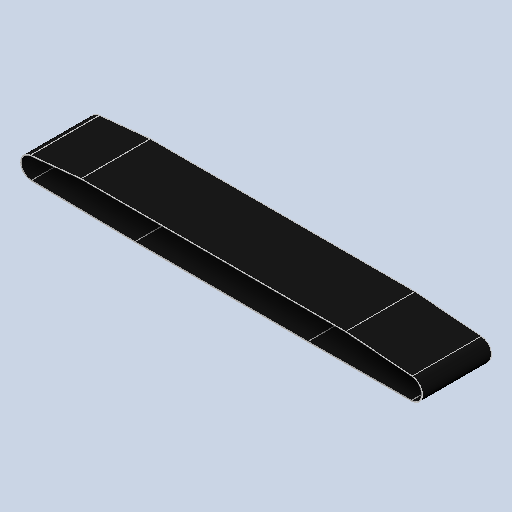
# Autodesk Inventor part: Banda
Saved by Autodesk Inventor 2025.3 (Build 293356000, 356)
## iProperties
Created: 2026-09-16
Part Number: Banda
Material: Hule SBR reforzado con tela
Document SubType Name: Modeling
Designer: ASUS
Density: 1.33 g/cm^3
Appearance: Hule negro mate - grano fino
Mass: 159.181 g
Surface Area: 2417.64 cm^2
Volume: 119.685 cm^3
Author: ASUS
Autodesk Inventor part; units mm, degrees
ref_plane "YZ Plane" through (0, 0, 0) normal (1, 0, 0) x (0, 1, 0)
ref_plane "XZ Plane" through (0, 0, 0) normal (0, 1, 0) x (-1, 0, 0)
ref_plane "XY Plane" through (0, 0, 0) normal (0, 0, 1) x (1, 0, 0)
sketch "Boceto1" plane through (0, 0, 0) normal (0, 0, 1) x (1, 0, 0)
  arc A0 (275.2379, 12.4594) -> (275.308, 45.9161) centre (275.308, 29.1877) ccw
  line L0 (275.2379, 12.4594) -> (-274.7368, 12.4594)
  arc A1 (-274.7368, 45.4594) -> (-274.7368, 12.4594) centre (-274.7368, 28.9594) ccw
  line L1 (275.308, 45.9161) -> (275.308, 45.9161)
  line L2 (-214.7369, 51.8594) -> (194.2632, 51.8594)
  line L3 (-274.7368, 45.4594) -> (-214.7369, 51.8594)
  line L4 (194.2632, 51.8594) -> (275.308, 45.9161)
  point P0 (0, 0)
  point P1 (0, 13.9594)
  constraints: 10 end point, 5 point on circle, 2 centre point, 1 horizontal, 1 vertical alignment
extrude "Extrusión1" [suppressed]
sketch "Boceto4" plane through (0, 0, 100) normal (0, 0, 1) x (1, 0, 0)
  arc A0 (-274.7368, 45.4594) -> (-274.7368, 12.4594) centre (-274.7368, 28.9594) ccw projected
  line L0 (-274.7368, 45.4594) -> (-274.7368, 44.4594)
  line L1 (-274.7368, 12.4594) -> (-274.7368, 13.4594)
  arc A1 (-274.7368, 44.4594) -> (-274.7368, 13.4594) centre (-274.7368, 28.9594) ccw
  arc A2 (275.2379, 12.4594) -> (275.308, 45.9161) centre (275.308, 29.1877) ccw projected
  line L2 (275.308, 45.9161) -> (275.308, 44.9161)
  line L3 (275.2379, 12.4594) -> (275.2379, 13.4594)
  arc A3 (275.2379, 13.4594) -> (275.308, 44.9161) centre (275.0173, 29.1883) ccw
  line L4 (-274.7368, 12.4594) -> (275.2379, 12.4594) projected
  line L5 (275.2379, 13.4594) -> (-274.7368, 13.4594)
  line L6 (-214.7369, 50.8594) -> (194.2632, 50.8594)
  line L7 (-274.7368, 44.4594) -> (-214.7369, 50.8594)
  line L8 (194.2632, 50.8594) -> (275.308, 44.9161)
  point P0 (0, 0)
  dimension "d35" = 1
  dimension "d36" = 1
  dimension "d39" = 1
  dimension "d40" = 1
  constraints: 16 end point, 4 point on circle, 4 vertical, 2 centre point, 1 horizontal
  measures "d35" distance of L0.start L0.end
  measures "d36" distance of L1.start L1.end
  measures "d39" distance of L2.start L2.end
  measures "d40" distance of L3.start L3.end
extrude "Extrusión3" [suppressed]
ref_plane "Lateral de banda · recorrido de lazo" through (276.4685, -14.0317, 0.2644) normal (0, 0, 1) x (0.9999888, 0.004727, 0)
sketch "Doble envolvente tangente de cinco rodillos" plane through (276.4685, -14.0317, 0.2644) normal (0, 0, 1) x (0.9999888, 0.004727, 0)
  arc A0 (-1.2784, 27.9979) -> (-1.2554, 57.9977) centre (-1.3254, 42.9978) ccw
  arc A1 (-550.6349, 60.5639) -> (-550.8922, 30.5653) centre (-550.705, 45.5641) ccw
  arc A2 (-401.1987, 28.6969) -> (-401.0894, 28.6959) centre (-401.024, 42.6958) ccw
  arc A3 (-151.0921, 27.5281) -> (-150.9828, 27.5281) centre (-151.0267, 41.528) ccw
  line L0 (-1.2554, 57.9977) -> (-550.6349, 60.5639)
  line L1 (-550.8922, 30.5653) -> (-401.1987, 28.6969)
  line L2 (-401.0894, 28.6959) -> (-151.0921, 27.5281)
  line L3 (-150.9828, 27.5281) -> (-1.2784, 27.9979)
  arc A4 (-1.2752, 26.9979) -> (-1.2507, 58.9976) centre (-1.3254, 42.9978) ccw
  arc A5 (-550.6303, 61.5639) -> (-550.9047, 29.5653) centre (-550.705, 45.5641) ccw
  arc A6 (-401.2112, 27.697) -> (-401.0941, 27.696) centre (-401.024, 42.6958) ccw
  arc A7 (-151.0968, 26.5282) -> (-150.9796, 26.5281) centre (-151.0267, 41.528) ccw
  line L4 (-1.2507, 58.9976) -> (-550.6303, 61.5639)
  line L5 (-550.9047, 29.5653) -> (-401.2112, 27.697)
  line L6 (-401.0941, 27.696) -> (-151.0968, 26.5282)
  line L7 (-150.9796, 26.5281) -> (-1.2752, 26.9979)
  constraints: 16 end point, 16 point on circle, 8 centre point
extrude "Recorrido transitorio previo a verificación de ejes" [suppressed]
ref_plane "Lateral de banda · ejes verificados" through (276.4685, -14.0317, 0.2644) normal (0, 0, 1) x (0.9999888, 0.004727, 0)
sketch "Envolvente de los cinco ejes verificados" plane through (276.4685, -14.0317, 0.2644) normal (0, 0, 1) x (0.9999888, 0.004727, 0)
  arc A0 (-1.2784, 27.9979) -> (-1.2365, 57.9976) centre (-1.3254, 42.9978) ccw
  arc A1 (-550.6128, 61.2562) -> (-550.9583, 31.2587) centre (-550.7018, 46.2565) ccw
  arc A2 (-401.2635, 28.6978) -> (-401.0894, 28.6959) centre (-401.024, 42.6958) ccw
  arc A3 (-151.0921, 27.5281) -> (-150.9828, 27.5281) centre (-151.0267, 41.528) ccw
  line L0 (-1.2365, 57.9976) -> (-550.6128, 61.2562)
  line L1 (-550.9583, 31.2587) -> (-401.2635, 28.6978)
  line L2 (-401.0894, 28.6959) -> (-151.0921, 27.5281)
  line L3 (-150.9828, 27.5281) -> (-1.2784, 27.9979)
  arc A4 (-1.2752, 26.9979) -> (-1.2305, 58.9975) centre (-1.3254, 42.9978) ccw
  arc A5 (-550.6069, 62.2562) -> (-550.9754, 30.2588) centre (-550.7018, 46.2565) ccw
  arc A6 (-401.2806, 27.698) -> (-401.0941, 27.696) centre (-401.024, 42.6958) ccw
  arc A7 (-151.0968, 26.5282) -> (-150.9796, 26.5281) centre (-151.0267, 41.528) ccw
  line L4 (-1.2305, 58.9975) -> (-550.6069, 62.2562)
  line L5 (-550.9754, 30.2588) -> (-401.2806, 27.698)
  line L6 (-401.0941, 27.696) -> (-151.0968, 26.5282)
  line L7 (-150.9796, 26.5281) -> (-1.2752, 26.9979)
  constraints: 16 end point, 16 point on circle, 8 centre point
extrude "Banda continua 100 × 1 mm" [suppressed]
ref_plane "Sección de banda con apoyos debajo" through (276.4685, -14.0317, 0.2644) normal (0, 0, 1) x (0.9999888, 0.004727, 0)
sketch "Envolvente cinco rodillos y seis apoyos" plane through (276.4685, -14.0317, 0.2644) normal (0, 0, 1) x (0.9999888, 0.004727, 0)
  arc A0 (-1.2784, 27.9979) -> (-0.0249, 57.9413) centre (-1.3254, 42.9978) ccw
  arc A1 (-552.1027, 61.1909) -> (-550.9583, 31.2587) centre (-550.7018, 46.2565) ccw
  arc A2 (-401.2635, 28.6978) -> (-401.0894, 28.6959) centre (-401.024, 42.6958) ccw
  arc A3 (-151.0921, 27.5281) -> (-150.9828, 27.5281) centre (-151.0267, 41.528) ccw
  line L0 (-0.0249, 57.9413) -> (-95.9105, 66.2861)
  line L1 (-95.9105, 66.2861) -> (-478.7262, 68.0743)
  line L2 (-478.7262, 68.0743) -> (-552.1027, 61.1909)
  line L3 (-550.9583, 31.2587) -> (-401.2635, 28.6978)
  line L4 (-401.0894, 28.6959) -> (-151.0921, 27.5281)
  line L5 (-150.9828, 27.5281) -> (-1.2784, 27.9979)
  arc A4 (-1.2752, 26.9979) -> (0.0618, 58.9376) centre (-1.3254, 42.9978) ccw
  arc A5 (-95.8238, 67.2823) -> (-95.9058, 67.2861) centre (-95.9105, 66.2861) ccw
  arc A6 (-478.7215, 69.0743) -> (-478.8196, 69.0699) centre (-478.7262, 68.0743) ccw
  arc A7 (-552.1961, 62.1865) -> (-550.9754, 30.2588) centre (-550.7018, 46.2565) ccw
  arc A8 (-401.2806, 27.698) -> (-401.0941, 27.696) centre (-401.024, 42.6958) ccw
  arc A9 (-151.0968, 26.5282) -> (-150.9796, 26.5281) centre (-151.0267, 41.528) ccw
  line L6 (0.0618, 58.9376) -> (-95.8238, 67.2823)
  line L7 (-95.9058, 67.2861) -> (-478.7215, 69.0743)
  line L8 (-478.8196, 69.0699) -> (-552.1961, 62.1865)
  line L9 (-550.9754, 30.2588) -> (-401.2806, 27.698)
  line L10 (-401.0941, 27.696) -> (-151.0968, 26.5282)
  line L11 (-150.9796, 26.5281) -> (-1.2752, 26.9979)
  constraints: 24 end point, 20 point on circle, 10 centre point
extrude "Banda SBR V2 sobre apoyos transversales" add sketch "Envolvente cinco rodillos y seis apoyos" along normal blind 100 separate body
